Autodesk Inventor part; units mm, degrees
(part 2 of 3)
  spline S257 degree 2 poles (-7.459, 30.0754) (-7.2586, 30.0754) (-7.0197, 30.2886) (-6.9657, 30.489) knots 0 0 0 1 2 2 2
  spline S258 degree 2 poles (-6.9657, 30.489) (-6.9298, 30.6226) (-6.8373, 31.0105) (-6.7988, 31.1389) knots 0 0 0 1 2 2 2
  spline S259 degree 2 poles (-6.7988, 31.1389) (-6.6986, 31.4652) (-6.2953, 31.7683) (-5.9998, 31.7683) knots 0 0 0 1 2 2 2
  spline S260 degree 2 poles (-5.9998, 31.7683) (-5.8123, 31.7683) (-5.4527, 31.6167) (-5.3268, 31.4806) knots 0 0 0 1 2 2 2
  spline S261 degree 2 poles (-5.3268, 31.4806) (-5.1881, 31.329) (-5.0391, 30.9437) (-5.0391, 30.6534) knots 0 0 0 1 2 2 2
  spline S262 degree 2 poles (-6.285, 34.1214) (-5.6839, 34.1214) (-5.0288, 33.5434) (-5.0288, 33.0604) knots 0 0 0 1 2 2 2
  spline S263 degree 2 poles (-5.0288, 33.0604) (-5.0288, 32.5647) (-5.7044, 31.9969) (-6.285, 31.9969) knots 0 0 0 1 2 2 2
  spline S264 degree 2 poles (-6.285, 31.9969) (-6.881, 31.9969) (-7.5412, 32.5826) (-7.5412, 33.0604) knots 0 0 0 1 2 2 2
  spline S265 degree 2 poles (-7.5412, 33.0604) (-7.5412, 33.5434) (-6.8835, 34.1214) (-6.285, 34.1214) knots 0 0 0 1 2 2 2
  spline S266 degree 2 poles (-6.285, 33.7078) (-6.7474, 33.7078) (-7.1969, 33.3713) (-7.1969, 33.0604) knots 0 0 0 1 2 2 2
  spline S267 degree 2 poles (-7.1969, 33.0604) (-7.1969, 32.7496) (-6.7474, 32.4105) (-6.285, 32.4105) knots 0 0 0 1 2 2 2
  spline S268 degree 2 poles (-6.285, 32.4105) (-5.8354, 32.4105) (-5.373, 32.7496) (-5.373, 33.0604) knots 0 0 0 1 2 2 2
  spline S269 degree 2 poles (-5.373, 33.0604) (-5.373, 33.3687) (-5.8277, 33.7078) (-6.285, 33.7078) knots 0 0 0 1 2 2 2
  spline S270 degree 2 poles (-5.0416, 35.4778) (-5.0416, 35.2312) (-5.1932, 34.8227) (-5.3473, 34.6763) knots 0 0 0 1 2 2 2
  spline S271 degree 2 poles (-5.3473, 34.6763) (-5.4989, 34.5298) (-5.9664, 34.368) (-6.2798, 34.368) knots 0 0 0 1 2 2 2
  spline S272 degree 2 poles (-6.2798, 34.368) (-6.5933, 34.368) (-7.0505, 34.535) (-7.2046, 34.6763) knots 0 0 0 1 2 2 2
  spline S273 degree 2 poles (-7.2046, 34.6763) (-7.3613, 34.8176) (-7.5283, 35.2363) (-7.5283, 35.4778) knots 0 0 0 1 2 2 2
  spline S274 degree 2 poles (-7.5283, 35.4778) (-7.5283, 35.673) (-7.4179, 36.0378) (-7.3459, 36.1791) knots 0 0 0 1 2 2 2
  line L206 (-7.3459, 36.1791) -> (-6.8964, 36.1791)
  line L207 (-6.8964, 36.1791) -> (-6.8964, 36.1559)
  spline S275 degree 2 poles (-6.8964, 36.1559) (-6.9323, 36.1123) (-7.0248, 35.9787) (-7.0736, 35.8836) knots 0 0 0 1 2 2 2
  spline S276 degree 2 poles (-7.0736, 35.8836) (-7.1147, 35.7989) (-7.179, 35.5728) (-7.179, 35.4701) knots 0 0 0 1 2 2 2
  spline S277 degree 2 poles (-7.179, 35.4701) (-7.179, 35.1592) (-6.7089, 34.7816) (-6.2798, 34.7816) knots 0 0 0 1 2 2 2
  spline S278 degree 2 poles (-6.2798, 34.7816) (-5.8611, 34.7816) (-5.391, 35.1464) (-5.391, 35.4701) knots 0 0 0 1 2 2 2
  spline S279 degree 2 poles (-5.391, 35.4701) (-5.391, 35.6653) (-5.5529, 36.0198) (-5.6787, 36.1559) knots 0 0 0 1 2 2 2
  line L208 (-5.6787, 36.1559) -> (-5.6787, 36.1791)
  line L209 (-5.6787, 36.1791) -> (-5.2292, 36.1791)
  spline S280 degree 2 poles (-5.2292, 36.1791) (-5.2009, 36.12) (-5.1213, 35.9402) (-5.1033, 35.8682) knots 0 0 0 1 2 2 2
  spline S281 degree 2 poles (-5.1033, 35.8682) (-5.0725, 35.7655) (-5.0416, 35.6036) (-5.0416, 35.4778) knots 0 0 0 1 2 2 2
  line L210 (0.1237, -6.4515) -> (0.1237, -8.4064)
  line L211 (0.1237, -8.4064) -> (-0.3258, -8.4064)
  spline S282 degree 2 poles (-0.3258, -8.4064) (-0.5236, -8.1958) (-0.891, -7.8207) (-1.0888, -7.6409) knots 0 0 0 1 2 2 2
  spline S283 degree 2 poles (-1.0888, -7.6409) (-1.487, -7.2787) (-1.9648, -7.0141) (-2.2191, -7.0141) knots 0 0 0 1 2 2 2
  spline S284 degree 2 poles (-2.2191, -7.0141) (-2.3527, -7.0141) (-2.553, -7.0963) (-2.6173, -7.1708) knots 0 0 0 1 2 2 2
  spline S285 degree 2 poles (-2.6173, -7.1708) (-2.6815, -7.2453) (-2.7457, -7.4405) (-2.7457, -7.5587) knots 0 0 0 1 2 2 2
  spline S286 degree 2 poles (-2.7457, -7.5587) (-2.7457, -7.6717) (-2.6892, -7.9029) (-2.6455, -8.0083) knots 0 0 0 1 2 2 2
  spline S287 degree 2 poles (-2.6455, -8.0083) (-2.6096, -8.0982) (-2.5068, -8.2652) (-2.4708, -8.3165) knots 0 0 0 1 2 2 2
  line L212 (-2.4708, -8.3165) -> (-2.4708, -8.3397)
  line L213 (-2.4708, -8.3397) -> (-2.923, -8.3397)
  spline S288 degree 2 poles (-2.923, -8.3397) (-2.9872, -8.2086) (-3.1131, -7.7385) (-3.1131, -7.5279) knots 0 0 0 1 2 2 2
  spline S289 degree 2 poles (-3.1131, -7.5279) (-3.1131, -7.0835) (-2.643, -6.5825) (-2.2422, -6.5825) knots 0 0 0 1 2 2 2
  spline S290 degree 2 poles (-2.2422, -6.5825) (-2.0547, -6.5825) (-1.7413, -6.6699) (-1.6077, -6.7469) knots 0 0 0 1 2 2 2
  spline S291 degree 2 poles (-1.6077, -6.7469) (-1.469, -6.824) (-1.1967, -7.0475) (-1.0657, -7.1708) knots 0 0 0 1 2 2 2
  spline S292 degree 2 poles (-1.0657, -7.1708) (-0.8473, -7.3712) (-0.3798, -7.8618) (-0.2436, -8.0083) knots 0 0 0 1 2 2 2
  line L214 (-0.2436, -8.0083) -> (-0.2436, -6.4515)
  line L215 (-0.2436, -6.4515) -> (0.1237, -6.4515)
  spline S293 degree 2 poles (-1.4613, -4.0548) (-0.6084, -4.0548) (0.1905, -4.5506) (0.1905, -5.0669) knots 0 0 0 1 2 2 2
  spline S294 degree 2 poles (0.1905, -5.0669) (0.1905, -5.5909) (-0.6238, -6.0816) (-1.4587, -6.0816) knots 0 0 0 1 2 2 2
  spline S295 degree 2 poles (-1.4587, -6.0816) (-2.3167, -6.0816) (-3.1105, -5.5858) (-3.1105, -5.0669) knots 0 0 0 1 2 2 2
  spline S296 degree 2 poles (-3.1105, -5.0669) (-3.1105, -4.5454) (-2.2885, -4.0548) (-1.4613, -4.0548) knots 0 0 0 1 2 2 2
  spline S297 degree 2 poles (-0.4954, -4.5994) (-0.6521, -4.5377) (-1.135, -4.4863) (-1.4613, -4.4863) knots 0 0 0 1 2 2 2
  spline S298 degree 2 poles (-1.4613, -4.4863) (-1.7875, -4.4863) (-2.2679, -4.5377) (-2.4297, -4.6019) knots 0 0 0 1 2 2 2
  spline S299 degree 2 poles (-2.4297, -4.6019) (-2.5916, -4.6662) (-2.7586, -4.8896) (-2.7586, -5.0669) knots 0 0 0 1 2 2 2
  spline S300 degree 2 poles (-2.7586, -5.0669) (-2.7586, -5.2441) (-2.5916, -5.4728) (-2.4246, -5.5396) knots 0 0 0 1 2 2 2
  spline S301 degree 2 poles (-2.4246, -5.5396) (-2.2628, -5.6038) (-1.7695, -5.65) (-1.4587, -5.65) knots 0 0 0 1 2 2 2
  spline S302 degree 2 poles (-1.4587, -5.65) (-1.1247, -5.65) (-0.6778, -5.6089) (-0.5031, -5.5421) knots 0 0 0 1 2 2 2
  spline S303 degree 2 poles (-0.5031, -5.5421) (-0.3387, -5.4805) (-0.1614, -5.2519) (-0.1614, -5.0669) knots 0 0 0 1 2 2 2
  spline S304 degree 2 poles (-0.1614, -5.0669) (-0.1614, -4.8922) (-0.3284, -4.6636) (-0.4954, -4.5994) knots 0 0 0 1 2 2 2
  line L216 (0.1237, -1.694) -> (0.1237, -3.6489)
  line L217 (0.1237, -3.6489) -> (-0.3258, -3.6489)
  spline S305 degree 2 poles (-0.3258, -3.6489) (-0.5236, -3.4382) (-0.891, -3.0632) (-1.0888, -2.8833) knots 0 0 0 1 2 2 2
  spline S306 degree 2 poles (-1.0888, -2.8833) (-1.487, -2.5211) (-1.9648, -2.2565) (-2.2191, -2.2565) knots 0 0 0 1 2 2 2
  spline S307 degree 2 poles (-2.2191, -2.2565) (-2.3527, -2.2565) (-2.553, -2.3387) (-2.6173, -2.4132) knots 0 0 0 1 2 2 2
  spline S308 degree 2 poles (-2.6173, -2.4132) (-2.6815, -2.4877) (-2.7457, -2.683) (-2.7457, -2.8011) knots 0 0 0 1 2 2 2
  spline S309 degree 2 poles (-2.7457, -2.8011) (-2.7457, -2.9142) (-2.6892, -3.1454) (-2.6455, -3.2507) knots 0 0 0 1 2 2 2
  spline S310 degree 2 poles (-2.6455, -3.2507) (-2.6096, -3.3406) (-2.5068, -3.5076) (-2.4708, -3.559) knots 0 0 0 1 2 2 2
  line L218 (-2.4708, -3.559) -> (-2.4708, -3.5821)
  line L219 (-2.4708, -3.5821) -> (-2.923, -3.5821)
  spline S311 degree 2 poles (-2.923, -3.5821) (-2.9872, -3.4511) (-3.1131, -2.981) (-3.1131, -2.7703) knots 0 0 0 1 2 2 2
  spline S312 degree 2 poles (-3.1131, -2.7703) (-3.1131, -2.3259) (-2.643, -1.825) (-2.2422, -1.825) knots 0 0 0 1 2 2 2
  spline S313 degree 2 poles (-2.2422, -1.825) (-2.0547, -1.825) (-1.7413, -1.9123) (-1.6077, -1.9894) knots 0 0 0 1 2 2 2
  spline S314 degree 2 poles (-1.6077, -1.9894) (-1.469, -2.0664) (-1.1967, -2.2899) (-1.0657, -2.4132) knots 0 0 0 1 2 2 2
  spline S315 degree 2 poles (-1.0657, -2.4132) (-0.8473, -2.6136) (-0.3798, -3.1043) (-0.2436, -3.2507) knots 0 0 0 1 2 2 2
  line L220 (-0.2436, -3.2507) -> (-0.2436, -1.694)
  line L221 (-0.2436, -1.694) -> (0.1237, -1.694)
  spline S316 degree 2 poles (-2.7457, -0.4147) (-2.7457, -0.5303) (-2.6892, -0.7589) (-2.6455, -0.8693) knots 0 0 0 1 2 2 2
  spline S317 degree 2 poles (-2.6455, -0.8693) (-2.6019, -0.9721) (-2.5094, -1.1237) (-2.4683, -1.1827) knots 0 0 0 1 2 2 2
  line L222 (-2.4683, -1.1827) -> (-2.4683, -1.2084)
  line L223 (-2.4683, -1.2084) -> (-2.9178, -1.2084)
  spline S318 degree 2 poles (-2.9178, -1.2084) (-2.9923, -1.0697) (-3.1131, -0.5945) (-3.1131, -0.3813) knots 0 0 0 1 2 2 2
  spline S319 degree 2 poles (-3.1131, -0.3813) (-3.1131, -0.1655) (-3.0257, 0.1556) (-2.9332, 0.2867) knots 0 0 0 1 2 2 2
  spline S320 degree 2 poles (-2.9332, 0.2867) (-2.8331, 0.4254) (-2.5428, 0.5692) (-2.3475, 0.5692) knots 0 0 0 1 2 2 2
  spline S321 degree 2 poles (-2.3475, 0.5692) (-2.0855, 0.5692) (-1.6899, 0.225) (-1.6385, -0.0165) knots 0 0 0 1 2 2 2
  line L224 (-1.6385, -0.0165) -> (-1.6077, -0.0165)
  spline S322 degree 2 poles (-1.6077, -0.0165) (-1.5871, 0.0837) (-1.4947, 0.3123) (-1.4022, 0.41) knots 0 0 0 1 2 2 2
  spline S323 degree 2 poles (-1.4022, 0.41) (-1.3123, 0.5076) (-1.0246, 0.6309) (-0.8165, 0.6309) knots 0 0 0 1 2 2 2
  spline S324 degree 2 poles (-0.8165, 0.6309) (-0.6033, 0.6309) (-0.2411, 0.4845) (-0.1023, 0.3509) knots 0 0 0 1 2 2 2
  spline S325 degree 2 poles (-0.1023, 0.3509) (0.0415, 0.2122) (0.1905, -0.1809) (0.1905, -0.4301) knots 0 0 0 1 2 2 2
  spline S326 degree 2 poles (0.1905, -0.4301) (0.1905, -0.669) (0.0749, -1.1365) (-0.0047, -1.2958) knots 0 0 0 1 2 2 2
  line L225 (-0.0047, -1.2958) -> (-0.4543, -1.2958)
  line L226 (-0.4543, -1.2958) -> (-0.4543, -1.265)
  spline S327 degree 2 poles (-0.4543, -1.265) (-0.3567, -1.1314) (-0.1768, -0.6792) (-0.1768, -0.4558) knots 0 0 0 1 2 2 2
  spline S328 degree 2 poles (-0.1768, -0.4558) (-0.1768, -0.3247) (-0.259, -0.0627) (-0.3541, 0.0246) knots 0 0 0 1 2 2 2
  spline S329 degree 2 poles (-0.3541, 0.0246) (-0.4491, 0.1094) (-0.6752, 0.1993) (-0.8473, 0.1993) knots 0 0 0 1 2 2 2
  spline S330 degree 2 poles (-0.8473, 0.1993) (-1.0194, 0.1993) (-1.2429, 0.0991) (-1.3071, 0.0092) knots 0 0 0 1 2 2 2
  spline S331 degree 2 poles (-1.3071, 0.0092) (-1.3714, -0.0807) (-1.4202, -0.3247) (-1.4202, -0.4686) knots 0 0 0 1 2 2 2
  line L227 (-1.4202, -0.4686) -> (-1.4202, -0.6484)
  line L228 (-1.4202, -0.6484) -> (-1.7721, -0.6484)
  line L229 (-1.7721, -0.6484) -> (-1.7721, -0.5071)
  spline S332 degree 2 poles (-1.7721, -0.5071) (-1.7721, -0.222) (-2.0444, 0.1377) (-2.3039, 0.1377) knots 0 0 0 1 2 2 2
  spline S333 degree 2 poles (-2.3039, 0.1377) (-2.4246, 0.1377) (-2.5967, 0.0452) (-2.6481, -0.0293) knots 0 0 0 1 2 2 2
  spline S334 degree 2 poles (-2.6481, -0.0293) (-2.702, -0.109) (-2.7457, -0.3042) (-2.7457, -0.4147) knots 0 0 0 1 2 2 2
  spline S335 degree 2 poles (-2.7457, 1.9641) (-2.7457, 1.8485) (-2.6892, 1.6199) (-2.6455, 1.5094) knots 0 0 0 1 2 2 2
  spline S336 degree 2 poles (-2.6455, 1.5094) (-2.6019, 1.4067) (-2.5094, 1.2551) (-2.4683, 1.196) knots 0 0 0 1 2 2 2
  line L230 (-2.4683, 1.196) -> (-2.4683, 1.1703)
  line L231 (-2.4683, 1.1703) -> (-2.9178, 1.1703)
  spline S337 degree 2 poles (-2.9178, 1.1703) (-2.9923, 1.3091) (-3.1131, 1.7843) (-3.1131, 1.9975) knots 0 0 0 1 2 2 2
  spline S338 degree 2 poles (-3.1131, 1.9975) (-3.1131, 2.2133) (-3.0257, 2.5344) (-2.9332, 2.6654) knots 0 0 0 1 2 2 2
  spline S339 degree 2 poles (-2.9332, 2.6654) (-2.8331, 2.8042) (-2.5428, 2.948) (-2.3475, 2.948) knots 0 0 0 1 2 2 2
  spline S340 degree 2 poles (-2.3475, 2.948) (-2.0855, 2.948) (-1.6899, 2.6038) (-1.6385, 2.3623) knots 0 0 0 1 2 2 2
  line L232 (-1.6385, 2.3623) -> (-1.6077, 2.3623)
  spline S341 degree 2 poles (-1.6077, 2.3623) (-1.5871, 2.4625) (-1.4947, 2.6911) (-1.4022, 2.7887) knots 0 0 0 1 2 2 2
  spline S342 degree 2 poles (-1.4022, 2.7887) (-1.3123, 2.8864) (-1.0246, 3.0097) (-0.8165, 3.0097) knots 0 0 0 1 2 2 2
  spline S343 degree 2 poles (-0.8165, 3.0097) (-0.6033, 3.0097) (-0.2411, 2.8632) (-0.1023, 2.7297) knots 0 0 0 1 2 2 2
  spline S344 degree 2 poles (-0.1023, 2.7297) (0.0415, 2.5909) (0.1905, 2.1979) (0.1905, 1.9487) knots 0 0 0 1 2 2 2
  spline S345 degree 2 poles (0.1905, 1.9487) (0.1905, 1.7098) (0.0749, 1.2423) (-0.0047, 1.083) knots 0 0 0 1 2 2 2
  line L233 (-0.0047, 1.083) -> (-0.4543, 1.083)
  line L234 (-0.4543, 1.083) -> (-0.4543, 1.1138)
  spline S346 degree 2 poles (-0.4543, 1.1138) (-0.3567, 1.2474) (-0.1768, 1.6995) (-0.1768, 1.923) knots 0 0 0 1 2 2 2
  spline S347 degree 2 poles (-0.1768, 1.923) (-0.1768, 2.054) (-0.259, 2.3161) (-0.3541, 2.4034) knots 0 0 0 1 2 2 2
  spline S348 degree 2 poles (-0.3541, 2.4034) (-0.4491, 2.4882) (-0.6752, 2.5781) (-0.8473, 2.5781) knots 0 0 0 1 2 2 2
  spline S349 degree 2 poles (-0.8473, 2.5781) (-1.0194, 2.5781) (-1.2429, 2.4779) (-1.3071, 2.388) knots 0 0 0 1 2 2 2
  spline S350 degree 2 poles (-1.3071, 2.388) (-1.3714, 2.2981) (-1.4202, 2.054) (-1.4202, 1.9102) knots 0 0 0 1 2 2 2
  line L235 (-1.4202, 1.9102) -> (-1.4202, 1.7304)
  line L236 (-1.4202, 1.7304) -> (-1.7721, 1.7304)
  line L237 (-1.7721, 1.7304) -> (-1.7721, 1.8717)
  spline S351 degree 2 poles (-1.7721, 1.8717) (-1.7721, 2.1568) (-2.0444, 2.5164) (-2.3039, 2.5164) knots 0 0 0 1 2 2 2
  spline S352 degree 2 poles (-2.3039, 2.5164) (-2.4246, 2.5164) (-2.5967, 2.424) (-2.6481, 2.3495) knots 0 0 0 1 2 2 2
  spline S353 degree 2 poles (-2.6481, 2.3495) (-2.702, 2.2698) (-2.7457, 2.0746) (-2.7457, 1.9641) knots 0 0 0 1 2 2 2
  spline S354 degree 2 poles (-1.4613, 5.4604) (-0.6084, 5.4604) (0.1905, 4.9646) (0.1905, 4.4482) knots 0 0 0 1 2 2 2
  spline S355 degree 2 poles (0.1905, 4.4482) (0.1905, 3.9242) (-0.6238, 3.4335) (-1.4587, 3.4335) knots 0 0 0 1 2 2 2
  spline S356 degree 2 poles (-1.4587, 3.4335) (-2.3167, 3.4335) (-3.1105, 3.9293) (-3.1105, 4.4482) knots 0 0 0 1 2 2 2
  spline S357 degree 2 poles (-3.1105, 4.4482) (-3.1105, 4.9697) (-2.2885, 5.4604) (-1.4613, 5.4604) knots 0 0 0 1 2 2 2
  spline S358 degree 2 poles (-0.4954, 4.9158) (-0.6521, 4.9774) (-1.135, 5.0288) (-1.4613, 5.0288) knots 0 0 0 1 2 2 2
  spline S359 degree 2 poles (-1.4613, 5.0288) (-1.7875, 5.0288) (-2.2679, 4.9774) (-2.4297, 4.9132) knots 0 0 0 1 2 2 2
  spline S360 degree 2 poles (-2.4297, 4.9132) (-2.5916, 4.849) (-2.7586, 4.6255) (-2.7586, 4.4482) knots 0 0 0 1 2 2 2
  spline S361 degree 2 poles (-2.7586, 4.4482) (-2.7586, 4.271) (-2.5916, 4.0424) (-2.4246, 3.9756) knots 0 0 0 1 2 2 2
  spline S362 degree 2 poles (-2.4246, 3.9756) (-2.2628, 3.9113) (-1.7695, 3.8651) (-1.4587, 3.8651) knots 0 0 0 1 2 2 2
  spline S363 degree 2 poles (-1.4587, 3.8651) (-1.1247, 3.8651) (-0.6778, 3.9062) (-0.5031, 3.973) knots 0 0 0 1 2 2 2
  spline S364 degree 2 poles (-0.5031, 3.973) (-0.3387, 4.0347) (-0.1614, 4.2633) (-0.1614, 4.4482) knots 0 0 0 1 2 2 2
  spline S365 degree 2 poles (-0.1614, 4.4482) (-0.1614, 4.6229) (-0.3284, 4.8516) (-0.4954, 4.9158) knots 0 0 0 1 2 2 2
  spline S366 degree 2 poles (-2.7457, 6.7217) (-2.7457, 6.6061) (-2.6892, 6.3775) (-2.6455, 6.267) knots 0 0 0 1 2 2 2
  spline S367 degree 2 poles (-2.6455, 6.267) (-2.6019, 6.1643) (-2.5094, 6.0127) (-2.4683, 5.9536) knots 0 0 0 1 2 2 2
  line L238 (-2.4683, 5.9536) -> (-2.4683, 5.9279)
  line L239 (-2.4683, 5.9279) -> (-2.9178, 5.9279)
  spline S368 degree 2 poles (-2.9178, 5.9279) (-2.9923, 6.0666) (-3.1131, 6.5419) (-3.1131, 6.7551) knots 0 0 0 1 2 2 2
  spline S369 degree 2 poles (-3.1131, 6.7551) (-3.1131, 6.9709) (-3.0257, 7.292) (-2.9332, 7.423) knots 0 0 0 1 2 2 2
  spline S370 degree 2 poles (-2.9332, 7.423) (-2.8331, 7.5617) (-2.5428, 7.7056) (-2.3475, 7.7056) knots 0 0 0 1 2 2 2
  spline S371 degree 2 poles (-2.3475, 7.7056) (-2.0855, 7.7056) (-1.6899, 7.3614) (-1.6385, 7.1199) knots 0 0 0 1 2 2 2
  line L240 (-1.6385, 7.1199) -> (-1.6077, 7.1199)
  spline S372 degree 2 poles (-1.6077, 7.1199) (-1.5871, 7.2201) (-1.4947, 7.4487) (-1.4022, 7.5463) knots 0 0 0 1 2 2 2
  spline S373 degree 2 poles (-1.4022, 7.5463) (-1.3123, 7.6439) (-1.0246, 7.7672) (-0.8165, 7.7672) knots 0 0 0 1 2 2 2
  spline S374 degree 2 poles (-0.8165, 7.7672) (-0.6033, 7.7672) (-0.2411, 7.6208) (-0.1023, 7.4872) knots 0 0 0 1 2 2 2
  spline S375 degree 2 poles (-0.1023, 7.4872) (0.0415, 7.3485) (0.1905, 6.9555) (0.1905, 6.7063) knots 0 0 0 1 2 2 2
  spline S376 degree 2 poles (0.1905, 6.7063) (0.1905, 6.4674) (0.0749, 5.9998) (-0.0047, 5.8406) knots 0 0 0 1 2 2 2
  line L241 (-0.0047, 5.8406) -> (-0.4543, 5.8406)
  line L242 (-0.4543, 5.8406) -> (-0.4543, 5.8714)
  spline S377 degree 2 poles (-0.4543, 5.8714) (-0.3567, 6.005) (-0.1768, 6.4571) (-0.1768, 6.6806) knots 0 0 0 1 2 2 2
  spline S378 degree 2 poles (-0.1768, 6.6806) (-0.1768, 6.8116) (-0.259, 7.0736) (-0.3541, 7.161) knots 0 0 0 1 2 2 2
  spline S379 degree 2 poles (-0.3541, 7.161) (-0.4491, 7.2458) (-0.6752, 7.3357) (-0.8473, 7.3357) knots 0 0 0 1 2 2 2
  spline S380 degree 2 poles (-0.8473, 7.3357) (-1.0194, 7.3357) (-1.2429, 7.2355) (-1.3071, 7.1456) knots 0 0 0 1 2 2 2
  spline S381 degree 2 poles (-1.3071, 7.1456) (-1.3714, 7.0557) (-1.4202, 6.8116) (-1.4202, 6.6678) knots 0 0 0 1 2 2 2
  line L243 (-1.4202, 6.6678) -> (-1.4202, 6.4879)
  line L244 (-1.4202, 6.4879) -> (-1.7721, 6.4879)
  line L245 (-1.7721, 6.4879) -> (-1.7721, 6.6292)
  spline S382 degree 2 poles (-1.7721, 6.6292) (-1.7721, 6.9144) (-2.0444, 7.274) (-2.3039, 7.274) knots 0 0 0 1 2 2 2
  spline S383 degree 2 poles (-2.3039, 7.274) (-2.4246, 7.274) (-2.5967, 7.1815) (-2.6481, 7.107) knots 0 0 0 1 2 2 2
  spline S384 degree 2 poles (-2.6481, 7.107) (-2.702, 7.0274) (-2.7457, 6.8322) (-2.7457, 6.7217) knots 0 0 0 1 2 2 2
  spline S385 degree 2 poles (0.1957, 9.2032) (0.1957, 8.9669) (0.0544, 8.579) (-0.0766, 8.4429) knots 0 0 0 1 2 2 2
  spline S386 degree 2 poles (-0.0766, 8.4429) (-0.2051, 8.3093) (-0.5545, 8.1706) (-0.7523, 8.1706) knots 0 0 0 1 2 2 2
  spline S387 degree 2 poles (-0.7523, 8.1706) (-1.0091, 8.1706) (-1.4407, 8.4454) (-1.5692, 8.7074) knots 0 0 0 1 2 2 2
  line L246 (-1.5692, 8.7074) -> (-1.582, 8.7074)
  spline S388 degree 2 poles (-1.582, 8.7074) (-1.7182, 8.4737) (-2.0418, 8.2476) (-2.2833, 8.2476) knots 0 0 0 1 2 2 2
  spline S389 degree 2 poles (-2.2833, 8.2476) (-2.6404, 8.2476) (-3.1182, 8.7871) (-3.1182, 9.2032) knots 0 0 0 1 2 2 2
  spline S390 degree 2 poles (-3.1182, 9.2032) (-3.1182, 9.6348) (-2.6661, 10.1563) (-2.3116, 10.1563) knots 0 0 0 1 2 2 2
  spline S391 degree 2 poles (-2.3116, 10.1563) (-2.0984, 10.1563) (-1.6822, 9.9071) (-1.564, 9.6733) knots 0 0 0 1 2 2 2
  line L247 (-1.564, 9.6733) -> (-1.5512, 9.6733)
  spline S392 degree 2 poles (-1.5512, 9.6733) (-1.4227, 9.9508) (-1.0528, 10.2359) (-0.76, 10.2359) knots 0 0 0 1 2 2 2
  spline S393 degree 2 poles (-0.76, 10.2359) (-0.3541, 10.2359) (0.1957, 9.6451) (0.1957, 9.2032) knots 0 0 0 1 2 2 2
  spline S394 degree 2 poles (-0.7189, 9.7992) (-0.9141, 9.7992) (-1.1453, 9.6451) (-1.2635, 9.4267) knots 0 0 0 1 2 2 2
  spline S395 degree 2 poles (-1.2635, 9.4267) (-1.3046, 9.3548) (-1.3996, 9.1133) (-1.4613, 8.9618) knots 0 0 0 1 2 2 2
  spline S396 degree 2 poles (-1.4613, 8.9618) (-1.3457, 8.7871) (-1.0014, 8.5996) (-0.7831, 8.5996) knots 0 0 0 1 2 2 2
  spline S397 degree 2 poles (-0.7831, 8.5996) (-0.4954, 8.5996) (-0.1203, 8.9464) (-0.1203, 9.2084) knots 0 0 0 1 2 2 2
  spline S398 degree 2 poles (-0.1203, 9.2084) (-0.1203, 9.4755) (-0.4414, 9.7992) (-0.7189, 9.7992) knots 0 0 0 1 2 2 2
  spline S399 degree 2 poles (-2.3064, 9.7401) (-2.5197, 9.7401) (-2.8048, 9.455) (-2.8048, 9.2007) knots 0 0 0 1 2 2 2
  spline S400 degree 2 poles (-2.8048, 9.2007) (-2.8048, 8.9695) (-2.5505, 8.6741) (-2.3321, 8.6741) knots 0 0 0 1 2 2 2
  spline S401 degree 2 poles (-2.3321, 8.6741) (-2.1754, 8.6741) (-1.9571, 8.8256) (-1.8697, 8.9772) knots 0 0 0 1 2 2 2
  spline S402 degree 2 poles (-1.8697, 8.9772) (-1.8338, 9.0414) (-1.7079, 9.3137) (-1.6719, 9.4242) knots 0 0 0 1 2 2 2
  spline S403 degree 2 poles (-1.6719, 9.4242) (-1.8132, 9.6091) (-2.1138, 9.7401) (-2.3064, 9.7401) knots 0 0 0 1 2 2 2
  spline S404 degree 2 poles (-2.0162, 10.5365) (-2.2602, 10.5365) (-2.6661, 10.6958) (-2.8125, 10.8345) knots 0 0 0 1 2 2 2
  spline S405 degree 2 poles (-2.8125, 10.8345) (-2.9538, 10.9655) (-3.1105, 11.3483) (-3.1105, 11.5435) knots 0 0 0 1 2 2 2
  spline S406 degree 2 poles (-3.1105, 11.5435) (-3.1105, 11.7618) (-2.9641, 12.1164) (-2.8253, 12.2474) knots 0 0 0 1 2 2 2
  spline S407 degree 2 poles (-2.8253, 12.2474) (-2.6507, 12.4118) (-2.0855, 12.5916) (-1.6514, 12.5916) knots 0 0 0 1 2 2 2
  spline S408 degree 2 poles (-1.6514, 12.5916) (-1.2583, 12.5916) (-0.5545, 12.4143) (-0.3207, 12.2422) knots 0 0 0 1 2 2 2
  spline S409 degree 2 poles (-0.3207, 12.2422) (-0.0741, 12.0598) (0.1854, 11.5461) (0.1854, 11.171) knots 0 0 0 1 2 2 2
  spline S410 degree 2 poles (0.1854, 11.171) (0.1854, 11.0862) (0.1674, 10.8936) (0.1417, 10.8114) knots 0 0 0 1 2 2 2
  line L248 (0.1417, 10.8114) -> (-0.2667, 10.8114)
  line L249 (-0.2667, 10.8114) -> (-0.2667, 10.8319)
  spline S411 degree 2 poles (-0.2667, 10.8319) (-0.2359, 10.8859) (-0.182, 11.1119) (-0.182, 11.2275) knots 0 0 0 1 2 2 2
  spline S412 degree 2 poles (-0.182, 11.2275) (-0.182, 11.6437) (-0.7317, 12.1189) (-1.2403, 12.1523) knots 0 0 0 1 2 2 2
  spline S413 degree 2 poles (-1.2403, 12.1523) (-1.1247, 11.9828) (-1.0194, 11.6745) (-1.0194, 11.4921) knots 0 0 0 1 2 2 2
  spline S414 degree 2 poles (-1.0194, 11.4921) (-1.0194, 11.3174) (-1.0965, 11.0271) (-1.207, 10.8807) knots 0 0 0 1 2 2 2
  spline S415 degree 2 poles (-1.207, 10.8807) (-1.338, 10.7112) (-1.7361, 10.5365) (-2.0162, 10.5365) knots 0 0 0 1 2 2 2
  spline S416 degree 2 poles (-1.7464, 12.1626) (-2.0675, 12.1626) (-2.4734, 12.0444) (-2.5839, 11.9391) knots 0 0 0 1 2 2 2
  spline S417 degree 2 poles (-2.5839, 11.9391) (-2.6866, 11.8466) (-2.7637, 11.654) (-2.7637, 11.5409) knots 0 0 0 1 2 2 2
  spline S418 degree 2 poles (-2.7637, 11.5409) (-2.7637, 11.2789) (-2.3886, 10.9681) (-2.0341, 10.9681) knots 0 0 0 1 2 2 2
  spline S419 degree 2 poles (-2.0341, 10.9681) (-1.8338, 10.9681) (-1.5743, 11.0708) (-1.4818, 11.1838) knots 0 0 0 1 2 2 2
  spline S420 degree 2 poles (-1.4818, 11.1838) (-1.415, 11.2661) (-1.3714, 11.469) (-1.3714, 11.5872) knots 0 0 0 1 2 2 2
  spline S421 degree 2 poles (-1.3714, 11.5872) (-1.3714, 11.7233) (-1.4664, 12.0367) (-1.546, 12.1549) knots 0 0 0 1 2 2 2
  spline S422 degree 2 poles (-1.546, 12.1549) (-1.5769, 12.1575) (-1.6822, 12.1626) (-1.7464, 12.1626) knots 0 0 0 1 2 2 2
  line L250 (10.312, -23.8361) -> (10.312, -24.3622)
  line L251 (10.312, -24.3622) -> (8.8942, -25.4762)
  line L252 (8.8942, -25.4762) -> (9.0943, -25.6541)
  line L253 (9.0943, -25.6541) -> (10.312, -25.6541)
  line L254 (10.312, -25.6541) -> (10.312, -26.0591)
  line L255 (10.312, -26.0591) -> (7.264, -26.0591)
  line L256 (7.264, -26.0591) -> (7.264, -25.6541)
  line L257 (7.264, -25.6541) -> (8.6645, -25.6541)
  line L258 (8.6645, -25.6541) -> (7.264, -24.4042)
  line L259 (7.264, -24.4042) -> (7.264, -23.9102)
  line L260 (7.264, -23.9102) -> (8.625, -25.1724)
  line L261 (8.625, -25.1724) -> (10.312, -23.8361)
  spline S423 degree 2 poles (10.3639, -22.6308) (10.3639, -23.1791) (9.7488, -23.7818) (9.1807, -23.7818) knots 0 0 0 1 2 2 2
  spline S424 degree 2 poles (9.1807, -23.7818) (8.6225, -23.7818) (7.9606, -23.1964) (7.9606, -22.7246) knots 0 0 0 1 2 2 2
  spline S425 degree 2 poles (7.9606, -22.7246) (7.9606, -22.5122) (8.0841, -22.1837) (8.215, -22.0627) knots 0 0 0 1 2 2 2
  spline S426 degree 2 poles (8.215, -22.0627) (8.3459, -21.9392) (8.7238, -21.8082) (8.998, -21.8082) knots 0 0 0 1 2 2 2
  line L262 (8.998, -21.8082) -> (9.2079, -21.8082)
  line L263 (9.2079, -21.8082) -> (9.2079, -23.3915)
  spline S427 degree 2 poles (9.2079, -23.3915) (9.6056, -23.3915) (10.028, -22.9914) (10.028, -22.6357) knots 0 0 0 1 2 2 2
  spline S428 degree 2 poles (10.028, -22.6357) (10.028, -22.5097) (9.9712, -22.2652) (9.9267, -22.1664) knots 0 0 0 1 2 2 2
  spline S429 degree 2 poles (9.9267, -22.1664) (9.8773, -22.0627) (9.7908, -21.9194) (9.7513, -21.8725) knots 0 0 0 1 2 2 2
  line L264 (9.7513, -21.8725) -> (9.7513, -21.8502)
  line L265 (9.7513, -21.8502) -> (10.1712, -21.8502)
  spline S430 degree 2 poles (10.1712, -21.8502) (10.1984, -21.9169) (10.2774, -22.1195) (10.2997, -22.1985) knots 0 0 0 1 2 2 2
  spline S431 degree 2 poles (10.2997, -22.1985) (10.3318, -22.3097) (10.3639, -22.4924) (10.3639, -22.6308) knots 0 0 0 1 2 2 2
  spline S432 degree 2 poles (8.914, -22.1837) (8.7584, -22.1886) (8.5311, -22.2528) (8.4546, -22.3146) knots 0 0 0 1 2 2 2
  spline S433 degree 2 poles (8.4546, -22.3146) (8.3681, -22.3813) (8.2767, -22.5912) (8.2767, -22.7469) knots 0 0 0 1 2 2 2
  spline S434 degree 2 poles (8.2767, -22.7469) (8.2767, -22.9) (8.3681, -23.1149) (8.457, -23.2038) knots 0 0 0 1 2 2 2
  spline S435 degree 2 poles (8.457, -23.2038) (8.5484, -23.2903) (8.7683, -23.3792) (8.914, -23.3915) knots 0 0 0 1 2 2 2
  line L266 (8.914, -23.3915) -> (8.914, -22.1837)
  line L267 (10.312, -19.6223) -> (10.312, -20.0076)
  line L268 (10.312, -20.0076) -> (9.0078, -20.0076)
  spline S436 degree 2 poles (9.0078, -20.0076) (8.8498, -20.0076) (8.5781, -20.0372) (8.4966, -20.0817) knots 0 0 0 1 2 2 2
  spline S437 degree 2 poles (8.4966, -20.0817) (8.4101, -20.1286) (8.3261, -20.2966) (8.3261, -20.4399) knots 0 0 0 1 2 2 2
  spline S438 degree 2 poles (8.3261, -20.4399) (8.3261, -20.5831) (8.4793, -20.8869) (8.6028, -21.0327) knots 0 0 0 1 2 2 2
  line L269 (8.6028, -21.0327) -> (10.312, -21.0327)
  line L270 (10.312, -21.0327) -> (10.312, -21.418)
  line L271 (10.312, -21.418) -> (8.0248, -21.418)
  line L272 (8.0248, -21.418) -> (8.0248, -21.0327)
  line L273 (8.0248, -21.0327) -> (8.2792, -21.0327)
  spline S439 degree 2 poles (8.2792, -21.0327) (8.1236, -20.8598) (7.9606, -20.5263) (7.9606, -20.3386) knots 0 0 0 1 2 2 2
  spline S440 degree 2 poles (7.9606, -20.3386) (7.9606, -20.0027) (8.4052, -19.6223) (8.8275, -19.6223) knots 0 0 0 1 2 2 2
  line L274 (8.8275, -19.6223) -> (10.312, -19.6223)
  line L275 (10.312, -17.2856) -> (10.312, -17.671)
  line L276 (10.312, -17.671) -> (9.0078, -17.671)
  spline S441 degree 2 poles (9.0078, -17.671) (8.8498, -17.671) (8.5781, -17.7006) (8.4966, -17.7451) knots 0 0 0 1 2 2 2
  spline S442 degree 2 poles (8.4966, -17.7451) (8.4101, -17.792) (8.3261, -17.96) (8.3261, -18.1032) knots 0 0 0 1 2 2 2
  spline S443 degree 2 poles (8.3261, -18.1032) (8.3261, -18.2465) (8.4793, -18.5503) (8.6028, -18.696) knots 0 0 0 1 2 2 2
  line L277 (8.6028, -18.696) -> (10.312, -18.696)
  line L278 (10.312, -18.696) -> (10.312, -19.0813)
  line L279 (10.312, -19.0813) -> (8.0248, -19.0813)
  line L280 (8.0248, -19.0813) -> (8.0248, -18.696)
  line L281 (8.0248, -18.696) -> (8.2792, -18.696)
  spline S444 degree 2 poles (8.2792, -18.696) (8.1236, -18.5231) (7.9606, -18.1897) (7.9606, -18.002) knots 0 0 0 1 2 2 2
  spline S445 degree 2 poles (7.9606, -18.002) (7.9606, -17.666) (8.4052, -17.2856) (8.8275, -17.2856) knots 0 0 0 1 2 2 2
  line L282 (8.8275, -17.2856) -> (10.312, -17.2856)
  line L283 (8.0248, -14.949) -> (11.1543, -16.1791)
  line L284 (11.1543, -16.1791) -> (11.1543, -16.5916)
  line L285 (11.1543, -16.5916) -> (10.2009, -16.1815)
  line L286 (10.2009, -16.1815) -> (8.0248, -17.0115)
  line L287 (8.0248, -17.0115) -> (8.0248, -16.5965)
  line L288 (8.0248, -16.5965) -> (9.7192, -15.9716)
  line L289 (9.7192, -15.9716) -> (8.0248, -15.3492)
  line L290 (8.0248, -15.3492) -> (8.0248, -14.949)
  line L291 (10.312, -13.6473) -> (7.264, -12.6198)
  line L292 (7.264, -12.6198) -> (7.264, -12.1208)
  line L293 (7.264, -12.1208) -> (10.312, -11.0933)
  line L294 (10.312, -11.0933) -> (10.312, -11.5206)
  line L295 (10.312, -11.5206) -> (9.4599, -11.7973)
  line L296 (9.4599, -11.7973) -> (9.4599, -12.9606)
  line L297 (9.4599, -12.9606) -> (10.312, -13.2373)
  line L298 (10.312, -13.2373) -> (10.312, -13.6473)
  line L299 (9.1141, -11.9084) -> (7.679, -12.3802)
  line L300 (7.679, -12.3802) -> (9.1141, -12.8495)
  line L301 (9.1141, -12.8495) -> (9.1141, -11.9084)
  line L302 (10.312, -10.4412) -> (10.312, -10.8266)
  line L303 (10.312, -10.8266) -> (7.1282, -10.8266)
  line L304 (7.1282, -10.8266) -> (7.1282, -10.4412)
  line L305 (7.1282, -10.4412) -> (10.312, -10.4412)
  spline S446 degree 2 poles (10.3639, -8.8827) (10.3639, -9.431) (9.7488, -10.0337) (9.1807, -10.0337) knots 0 0 0 1 2 2 2
  spline S447 degree 2 poles (9.1807, -10.0337) (8.6225, -10.0337) (7.9606, -9.4483) (7.9606, -8.9765) knots 0 0 0 1 2 2 2
  spline S448 degree 2 poles (7.9606, -8.9765) (7.9606, -8.7641) (8.0841, -8.4356) (8.215, -8.3145) knots 0 0 0 1 2 2 2
  spline S449 degree 2 poles (8.215, -8.3145) (8.3459, -8.191) (8.7238, -8.0601) (8.998, -8.0601) knots 0 0 0 1 2 2 2
  line L306 (8.998, -8.0601) -> (9.2079, -8.0601)
  line L307 (9.2079, -8.0601) -> (9.2079, -9.6434)
  spline S450 degree 2 poles (9.2079, -9.6434) (9.6056, -9.6434) (10.028, -9.2433) (10.028, -8.8876) knots 0 0 0 1 2 2 2
  spline S451 degree 2 poles (10.028, -8.8876) (10.028, -8.7616) (9.9712, -8.5171) (9.9267, -8.4183) knots 0 0 0 1 2 2 2
  spline S452 degree 2 poles (9.9267, -8.4183) (9.8773, -8.3145) (9.7908, -8.1713) (9.7513, -8.1244) knots 0 0 0 1 2 2 2
  line L308 (9.7513, -8.1244) -> (9.7513, -8.1021)
  line L309 (9.7513, -8.1021) -> (10.1712, -8.1021)
  spline S453 degree 2 poles (10.1712, -8.1021) (10.1984, -8.1688) (10.2774, -8.3714) (10.2997, -8.4504) knots 0 0 0 1 2 2 2
  spline S454 degree 2 poles (10.2997, -8.4504) (10.3318, -8.5615) (10.3639, -8.7443) (10.3639, -8.8827) knots 0 0 0 1 2 2 2
  spline S455 degree 2 poles (8.914, -8.4356) (8.7584, -8.4405) (8.5311, -8.5047) (8.4546, -8.5665) knots 0 0 0 1 2 2 2
  spline S456 degree 2 poles (8.4546, -8.5665) (8.3681, -8.6332) (8.2767, -8.8431) (8.2767, -8.9987) knots 0 0 0 1 2 2 2
  spline S457 degree 2 poles (8.2767, -8.9987) (8.2767, -9.1519) (8.3681, -9.3668) (8.457, -9.4557) knots 0 0 0 1 2 2 2
  spline S458 degree 2 poles (8.457, -9.4557) (8.5484, -9.5421) (8.7683, -9.6311) (8.914, -9.6434) knots 0 0 0 1 2 2 2
  line L310 (8.914, -9.6434) -> (8.914, -8.4356)
  line L311 (10.312, -5.8939) -> (10.312, -6.3657)
  line L312 (10.312, -6.3657) -> (9.4524, -6.9215)
  line L313 (9.4524, -6.9215) -> (10.312, -7.492)
  line L314 (10.312, -7.492) -> (10.312, -7.9292)
  line L315 (10.312, -7.9292) -> (9.1783, -7.1363)
  line L316 (9.1783, -7.1363) -> (8.0248, -7.9218)
  line L317 (8.0248, -7.9218) -> (8.0248, -7.45)
  line L318 (8.0248, -7.45) -> (8.8769, -6.8968)
  line L319 (8.8769, -6.8968) -> (8.0248, -6.3311)
  line L320 (8.0248, -6.3311) -> (8.0248, -5.8939)
  line L321 (8.0248, -5.8939) -> (9.1536, -6.6819)
  line L322 (9.1536, -6.6819) -> (10.312, -5.8939)
  spline S459 degree 2 poles (10.07, -4.3205) (10.1045, -4.3675) (10.228, -4.5255) (10.2651, -4.5996) knots 0 0 0 1 2 2 2
  spline S460 degree 2 poles (10.2651, -4.5996) (10.3194, -4.7009) (10.3762, -4.8911) (10.3762, -5.064) knots 0 0 0 1 2 2 2
  spline S461 degree 2 poles (10.3762, -5.064) (10.3762, -5.2048) (10.27, -5.4592) (10.1737, -5.5555) knots 0 0 0 1 2 2 2
  spline S462 degree 2 poles (10.1737, -5.5555) (10.0798, -5.6469) (9.8032, -5.7581) (9.65, -5.7581) knots 0 0 0 1 2 2 2
  spline S463 degree 2 poles (9.65, -5.7581) (9.4129, -5.7581) (9.077, -5.558) (8.9807, -5.3406) knots 0 0 0 1 2 2 2
  spline S464 degree 2 poles (8.9807, -5.3406) (8.8918, -5.148) (8.8251, -4.6243) (8.8078, -4.3205) knots 0 0 0 1 2 2 2
  line L323 (8.8078, -4.3205) -> (8.7337, -4.3205)
  spline S465 degree 2 poles (8.7337, -4.3205) (8.6003, -4.3205) (8.4348, -4.402) (8.3879, -4.4761) knots 0 0 0 1 2 2 2
  spline S466 degree 2 poles (8.3879, -4.4761) (8.3409, -4.5502) (8.3113, -4.7627) (8.3113, -4.8763) knots 0 0 0 1 2 2 2
  spline S467 degree 2 poles (8.3113, -4.8763) (8.3113, -5.0097) (8.3903, -5.3703) (8.4669, -5.5506) knots 0 0 0 1 2 2 2
  line L324 (8.4669, -5.5506) -> (8.4669, -5.5728)
  line L325 (8.4669, -5.5728) -> (8.0742, -5.5728)
  spline S468 degree 2 poles (8.0742, -5.5728) (8.0445, -5.4666) (7.9704, -5.0689) (7.9704, -4.8738) knots 0 0 0 1 2 2 2
  spline S469 degree 2 poles (7.9704, -4.8738) (7.9704, -4.6367) (8.0445, -4.3131) (8.1409, -4.1847) knots 0 0 0 1 2 2 2
  spline S470 degree 2 poles (8.1409, -4.1847) (8.2347, -4.0587) (8.5336, -3.9352) (8.7485, -3.9352) knots 0 0 0 1 2 2 2
  line L326 (8.7485, -3.9352) -> (10.312, -3.9352)
  line L327 (10.312, -3.9352) -> (10.312, -4.3205)
  line L328 (10.312, -4.3205) -> (10.07, -4.3205)
  line L329 (9.7488, -4.3205) -> (9.1141, -4.3205)
  spline S471 degree 2 poles (9.1141, -4.3205) (9.1264, -4.4589) (9.1684, -4.8763) (9.2079, -5.0072) knots 0 0 0 1 2 2 2
  spline S472 degree 2 poles (9.2079, -5.0072) (9.2548, -5.1603) (9.45, -5.3604) (9.6229, -5.3604) knots 0 0 0 1 2 2 2
  spline S473 degree 2 poles (9.6229, -5.3604) (9.8205, -5.3604) (10.0206, -5.1381) (10.0206, -4.9257) knots 0 0 0 1 2 2 2
  spline S474 degree 2 poles (10.0206, -4.9257) (10.0206, -4.7454) (9.8649, -4.449) (9.7488, -4.3205) knots 0 0 0 1 2 2 2
  line L330 (10.312, -1.5986) -> (10.312, -1.9839)
  line L331 (10.312, -1.9839) -> (9.0078, -1.9839)
  spline S475 degree 2 poles (9.0078, -1.9839) (8.8498, -1.9839) (8.5781, -2.0135) (8.4966, -2.058) knots 0 0 0 1 2 2 2
  spline S476 degree 2 poles (8.4966, -2.058) (8.4101, -2.1049) (8.3261, -2.2729) (8.3261, -2.4161) knots 0 0 0 1 2 2 2
  spline S477 degree 2 poles (8.3261, -2.4161) (8.3261, -2.5594) (8.4793, -2.8632) (8.6028, -3.009) knots 0 0 0 1 2 2 2
  line L332 (8.6028, -3.009) -> (10.312, -3.009)
  line L333 (10.312, -3.009) -> (10.312, -3.3943)
  line L334 (10.312, -3.3943) -> (8.0248, -3.3943)
  line L335 (8.0248, -3.3943) -> (8.0248, -3.009)
  line L336 (8.0248, -3.009) -> (8.2792, -3.009)
  spline S478 degree 2 poles (8.2792, -3.009) (8.1236, -2.8361) (7.9606, -2.5026) (7.9606, -2.3149) knots 0 0 0 1 2 2 2
  spline S479 degree 2 poles (7.9606, -2.3149) (7.9606, -1.979) (8.4052, -1.5986) (8.8275, -1.5986) knots 0 0 0 1 2 2 2
  line L337 (8.8275, -1.5986) -> (10.312, -1.5986)
  line L338 (10.312, 0.701) -> (10.312, 0.3157)
  line L339 (10.312, 0.3157) -> (10.0798, 0.3157)
  spline S480 degree 2 poles (10.0798, 0.3157) (10.1539, 0.2268) (10.2527, 0.0959) (10.2947, 0.0069) knots 0 0 0 1 2 2 2
  spline S481 degree 2 poles (10.2947, 0.0069) (10.3342, -0.0746) (10.3762, -0.2499) (10.3762, -0.366) knots 0 0 0 1 2 2 2
  spline S482 degree 2 poles (10.3762, -0.366) (10.3762, -0.5538) (10.2206, -0.8699) (10.07, -0.9811) knots 0 0 0 1 2 2 2
  spline S483 degree 2 poles (10.07, -0.9811) (9.9193, -1.0922) (9.4747, -1.2157) (9.1857, -1.2157) knots 0 0 0 1 2 2 2
  spline S484 degree 2 poles (9.1857, -1.2157) (8.8843, -1.2157) (8.4447, -1.0601) (8.2792, -0.9243) knots 0 0 0 1 2 2 2
  spline S485 degree 2 poles (8.2792, -0.9243) (8.131, -0.7983) (7.9606, -0.4451) (7.9606, -0.2499) knots 0 0 0 1 2 2 2
  spline S486 degree 2 poles (7.9606, -0.2499) (7.9606, -0.0795) (8.0371, 0.1749) (8.1162, 0.3157) knots 0 0 0 1 2 2 2
  line L340 (8.1162, 0.3157) -> (7.1282, 0.3157)
  line L341 (7.1282, 0.3157) -> (7.1282, 0.701)
  line L342 (7.1282, 0.701) -> (10.312, 0.701)
  line L343 (9.7563, 0.3157) -> (8.4348, 0.3157)
  spline S487 degree 2 poles (8.4348, 0.3157) (8.3656, 0.1724) (8.3138, -0.0548) (8.3138, -0.1857) knots 0 0 0 1 2 2 2
  spline S488 degree 2 poles (8.3138, -0.1857) (8.3138, -0.4821) (8.7584, -0.818) (9.1783, -0.818) knots 0 0 0 1 2 2 2
  spline S489 degree 2 poles (9.1783, -0.818) (9.5834, -0.818) (10.0107, -0.5612) (10.0107, -0.2771) knots 0 0 0 1 2 2 2
  spline S490 degree 2 poles (10.0107, -0.2771) (10.0107, -0.1264) (9.8724, 0.1798) (9.7563, 0.3157) knots 0 0 0 1 2 2 2
  line L344 (8.4373, 2.472) -> (8.4373, 2.4523)
  spline S491 degree 2 poles (8.4373, 2.4523) (8.4249, 2.4078) (8.42, 2.3115) (8.42, 2.2448) knots 0 0 0 1 2 2 2
  spline S492 degree 2 poles (8.42, 2.2448) (8.42, 2.0892) (8.5558, 1.7829) (8.6892, 1.6446) knots 0 0 0 1 2 2 2
  line L345 (8.6892, 1.6446) -> (10.312, 1.6446)
  line L346 (10.312, 1.6446) -> (10.312, 1.2592)
  line L347 (10.312, 1.2592) -> (8.0248, 1.2592)
  line L348 (8.0248, 1.2592) -> (8.0248, 1.6446)
  line L349 (8.0248, 1.6446) -> (8.3656, 1.6446)
  spline S493 degree 2 poles (8.3656, 1.6446) (8.1779, 1.8545) (8.0248, 2.1682) (8.0248, 2.3164) knots 0 0 0 1 2 2 2
  spline S494 degree 2 poles (8.0248, 2.3164) (8.0248, 2.3757) (8.0297, 2.435) (8.0371, 2.472) knots 0 0 0 1 2 2 2
  line L350 (8.0371, 2.472) -> (8.4373, 2.472)
  spline S495 degree 2 poles (9.1684, 4.6506) (9.7464, 4.6506) (10.3762, 4.0948) (10.3762, 3.6305) knots 0 0 0 1 2 2 2
  spline S496 degree 2 poles (10.3762, 3.6305) (10.3762, 3.1537) (9.7266, 2.6079) (9.1684, 2.6079) knots 0 0 0 1 2 2 2
  spline S497 degree 2 poles (9.1684, 2.6079) (8.5954, 2.6079) (7.9606, 3.171) (7.9606, 3.6305) knots 0 0 0 1 2 2 2
  spline S498 degree 2 poles (7.9606, 3.6305) (7.9606, 4.0948) (8.5929, 4.6506) (9.1684, 4.6506) knots 0 0 0 1 2 2 2
  spline S499 degree 2 poles (9.1684, 4.2529) (8.7238, 4.2529) (8.2915, 3.9293) (8.2915, 3.6305) knots 0 0 0 1 2 2 2
  spline S500 degree 2 poles (8.2915, 3.6305) (8.2915, 3.3316) (8.7238, 3.0055) (9.1684, 3.0055) knots 0 0 0 1 2 2 2
  spline S501 degree 2 poles (9.1684, 3.0055) (9.6006, 3.0055) (10.0453, 3.3316) (10.0453, 3.6305) knots 0 0 0 1 2 2 2
  spline S502 degree 2 poles (10.0453, 3.6305) (10.0453, 3.9269) (9.6081, 4.2529) (9.1684, 4.2529) knots 0 0 0 1 2 2 2
  spline S503 degree 2 poles (7.6123, 8.5408) (7.8148, 8.7137) (8.4076, 8.9064) (8.788, 8.9064) knots 0 0 0 1 2 2 2
  spline S504 degree 2 poles (8.788, 8.9064) (9.1585, 8.9064) (9.7587, 8.7187) (9.9613, 8.5408) knots 0 0 0 1 2 2 2
  spline S505 degree 2 poles (9.9613, 8.5408) (10.1737, 8.3531) (10.3762, 7.8566) (10.3762, 7.5578) knots 0 0 0 1 2 2 2
  spline S506 degree 2 poles (10.3762, 7.5578) (10.3762, 7.249) (10.1663, 6.755) (9.9613, 6.5747) knots 0 0 0 1 2 2 2
  spline S507 degree 2 poles (9.9613, 6.5747) (9.7587, 6.3993) (9.1635, 6.2116) (8.788, 6.2116) knots 0 0 0 1 2 2 2
  spline S508 degree 2 poles (8.788, 6.2116) (8.4052, 6.2116) (7.8222, 6.4018) (7.6123, 6.5772) knots 0 0 0 1 2 2 2
  spline S509 degree 2 poles (7.6123, 6.5772) (7.4097, 6.755) (7.1998, 7.2515) (7.1998, 7.5578) knots 0 0 0 1 2 2 2
  spline S510 degree 2 poles (7.1998, 7.5578) (7.1998, 7.869) (7.4172, 8.3679) (7.6123, 8.5408) knots 0 0 0 1 2 2 2
  spline S511 degree 2 poles (8.788, 8.484) (8.4867, 8.484) (8.0198, 8.3531) (7.8667, 8.2346) knots 0 0 0 1 2 2 2
  spline S512 degree 2 poles (7.8667, 8.2346) (7.7086, 8.1135) (7.5505, 7.7727) (7.5505, 7.5602) knots 0 0 0 1 2 2 2
  spline S513 degree 2 poles (7.5505, 7.5602) (7.5505, 7.3404) (7.7037, 7.0094) (7.8667, 6.8835) knots 0 0 0 1 2 2 2
  spline S514 degree 2 poles (7.8667, 6.8835) (8.0223, 6.7624) (8.4916, 6.634) (8.788, 6.634) knots 0 0 0 1 2 2 2
  spline S515 degree 2 poles (8.788, 6.634) (9.3882, 6.634) (10.0255, 7.1379) (10.0255, 7.5602) knots 0 0 0 1 2 2 2
  spline S516 degree 2 poles (10.0255, 7.5602) (10.0255, 7.9826) (9.3882, 8.484) (8.788, 8.484) knots 0 0 0 1 2 2 2
  line L351 (10.312, 11.0973) -> (10.312, 10.6255)
  line L352 (10.312, 10.6255) -> (9.4524, 10.0698)
  line L353 (9.4524, 10.0698) -> (10.312, 9.4992)
  line L354 (10.312, 9.4992) -> (10.312, 9.062)
  line L355 (10.312, 9.062) -> (9.1783, 9.8549)
  line L356 (9.1783, 9.8549) -> (8.0248, 9.0694)
  line L357 (8.0248, 9.0694) -> (8.0248, 9.5412)
  line L358 (8.0248, 9.5412) -> (8.8769, 10.0945)
  line L359 (8.8769, 10.0945) -> (8.0248, 10.6601)
  line L360 (8.0248, 10.6601) -> (8.0248, 11.0973)
  line L361 (8.0248, 11.0973) -> (9.1536, 10.3094)
  line L362 (9.1536, 10.3094) -> (10.312, 11.0973)
  line L363 (10.312, 11.7889) -> (10.312, 11.4036)
  line L364 (10.312, 11.4036) -> (7.1282, 11.4036)
  line L365 (7.1282, 11.4036) -> (7.1282, 11.7889)
  line L366 (7.1282, 11.7889) -> (10.312, 11.7889)
  spline S517 degree 2 poles (10.07, 13.6291) (10.1045, 13.5821) (10.228, 13.4241) (10.2651, 13.35) knots 0 0 0 1 2 2 2
  spline S518 degree 2 poles (10.2651, 13.35) (10.3194, 13.2487) (10.3762, 13.0585) (10.3762, 12.8856) knots 0 0 0 1 2 2 2
  spline S519 degree 2 poles (10.3762, 12.8856) (10.3762, 12.7448) (10.27, 12.4904) (10.1737, 12.3941) knots 0 0 0 1 2 2 2
  spline S520 degree 2 poles (10.1737, 12.3941) (10.0798, 12.3027) (9.8032, 12.1915) (9.65, 12.1915) knots 0 0 0 1 2 2 2
  spline S521 degree 2 poles (9.65, 12.1915) (9.4129, 12.1915) (9.077, 12.3916) (8.9807, 12.609) knots 0 0 0 1 2 2 2
  spline S522 degree 2 poles (8.9807, 12.609) (8.8918, 12.8016) (8.8251, 13.3253) (8.8078, 13.6291) knots 0 0 0 1 2 2 2
  line L367 (8.8078, 13.6291) -> (8.7337, 13.6291)
  spline S523 degree 2 poles (8.7337, 13.6291) (8.6003, 13.6291) (8.4348, 13.5476) (8.3879, 13.4735) knots 0 0 0 1 2 2 2
  spline S524 degree 2 poles (8.3879, 13.4735) (8.3409, 13.3994) (8.3113, 13.1869) (8.3113, 13.0733) knots 0 0 0 1 2 2 2
  spline S525 degree 2 poles (8.3113, 13.0733) (8.3113, 12.9399) (8.3903, 12.5793) (8.4669, 12.399) knots 0 0 0 1 2 2 2
  line L368 (8.4669, 12.399) -> (8.4669, 12.3768)
  line L369 (8.4669, 12.3768) -> (8.0742, 12.3768)
  spline S526 degree 2 poles (8.0742, 12.3768) (8.0445, 12.483) (7.9704, 12.8807) (7.9704, 13.0758) knots 0 0 0 1 2 2 2
  spline S527 degree 2 poles (7.9704, 13.0758) (7.9704, 13.3129) (8.0445, 13.6365) (8.1409, 13.7649) knots 0 0 0 1 2 2 2
  spline S528 degree 2 poles (8.1409, 13.7649) (8.2347, 13.8909) (8.5336, 14.0144) (8.7485, 14.0144) knots 0 0 0 1 2 2 2
  line L370 (8.7485, 14.0144) -> (10.312, 14.0144)
  line L371 (10.312, 14.0144) -> (10.312, 13.6291)
  line L372 (10.312, 13.6291) -> (10.07, 13.6291)
  line L373 (9.7488, 13.6291) -> (9.1141, 13.6291)
  spline S529 degree 2 poles (9.1141, 13.6291) (9.1264, 13.4908) (9.1684, 13.0733) (9.2079, 12.9424) knots 0 0 0 1 2 2 2
  spline S530 degree 2 poles (9.2079, 12.9424) (9.2548, 12.7893) (9.45, 12.5892) (9.6229, 12.5892) knots 0 0 0 1 2 2 2
  spline S531 degree 2 poles (9.6229, 12.5892) (9.8205, 12.5892) (10.0206, 12.8115) (10.0206, 13.0239) knots 0 0 0 1 2 2 2
  spline S532 degree 2 poles (10.0206, 13.0239) (10.0206, 13.2042) (9.8649, 13.5006) (9.7488, 13.6291) knots 0 0 0 1 2 2 2
  spline S533 degree 2 poles (10.3762, 15.1778) (10.7665, 15.1778) (11.1765, 14.7579) (11.1765, 14.3898) knots 0 0 0 1 2 2 2
  spline S534 degree 2 poles (11.1765, 14.3898) (11.1765, 14.3256) (11.1642, 14.1675) (11.1518, 14.091) knots 0 0 0 1 2 2 2
  line L374 (11.1518, 14.091) -> (10.806, 14.091)
  line L375 (10.806, 14.091) -> (10.806, 14.1132)
  spline S535 degree 2 poles (10.806, 14.1132) (10.8159, 14.1577) (10.8357, 14.2663) (10.8357, 14.3157) knots 0 0 0 1 2 2 2
  spline S536 degree 2 poles (10.8357, 14.3157) (10.8357, 14.4689) (10.7591, 14.669) (10.6776, 14.7159) knots 0 0 0 1 2 2 2
  spline S537 degree 2 poles (10.6776, 14.7159) (10.6035, 14.7628) (10.3787, 14.7925) (10.2182, 14.7925) knots 0 0 0 1 2 2 2
  line L376 (10.2182, 14.7925) -> (8.3434, 14.7925)
  line L377 (8.3434, 14.7925) -> (8.3434, 14.38)
  line L378 (8.3434, 14.38) -> (8.0248, 14.38)
  line L379 (8.0248, 14.38) -> (8.0248, 15.1778)
  line L380 (8.0248, 15.1778) -> (10.3762, 15.1778)
  line L381 (7.6444, 15.1802) -> (7.6444, 14.7431)
  line L382 (7.6444, 14.7431) -> (7.2443, 14.7431)
  line L383 (7.2443, 14.7431) -> (7.2443, 15.1802)
  line L384 (7.2443, 15.1802) -> (7.6444, 15.1802)
  line L385 (10.312, 17.7861) -> (7.6246, 17.7861)
  line L386 (7.6246, 17.7861) -> (7.6246, 16.7635)
  line L387 (7.6246, 16.7635) -> (7.264, 16.7635)
  line L388 (7.264, 16.7635) -> (7.264, 19.2138)
  line L389 (7.264, 19.2138) -> (7.6246, 19.2138)
  line L390 (7.6246, 19.2138) -> (7.6246, 18.1912)
  line L391 (7.6246, 18.1912) -> (10.312, 18.1912)
  line L392 (10.312, 18.1912) -> (10.312, 17.7861)
  line L393 (10.312, 20.9947) -> (10.312, 19.3151)
  line L394 (10.312, 19.3151) -> (10.0255, 19.3151)
  line L395 (10.0255, 19.3151) -> (8.3409, 20.5105)
  line L396 (8.3409, 20.5105) -> (8.3409, 19.3645)
  line L397 (8.3409, 19.3645) -> (8.0248, 19.3645)
  line L398 (8.0248, 19.3645) -> (8.0248, 20.9724)
  line L399 (8.0248, 20.9724) -> (8.299, 20.9724)
  line L400 (8.299, 20.9724) -> (9.9884, 19.772)
  line L401 (9.9884, 19.772) -> (9.9884, 20.9947)
  line L402 (9.9884, 20.9947) -> (10.312, 20.9947)
  line L403 (10.312, 23.1337) -> (10.312, 22.7484)
  line L404 (10.312, 22.7484) -> (10.0601, 22.7484)
  spline S538 degree 2 poles (10.0601, 22.7484) (10.2157, 22.5705) (10.3762, 22.2519) (10.3762, 22.0543) knots 0 0 0 1 2 2 2
  spline S539 degree 2 poles (10.3762, 22.0543) (10.3762, 21.9061) (10.2774, 21.6418) (10.1712, 21.5455) knots 0 0 0 1 2 2 2
  spline S540 degree 2 poles (10.1712, 21.5455) (10.065, 21.4467) (9.7414, 21.338) (9.5093, 21.338) knots 0 0 0 1 2 2 2
  line L405 (9.5093, 21.338) -> (8.0248, 21.338)
  line L406 (8.0248, 21.338) -> (8.0248, 21.7233)
  line L407 (8.0248, 21.7233) -> (9.3289, 21.7233)
  spline S541 degree 2 poles (9.3289, 21.7233) (9.5117, 21.7233) (9.7513, 21.7505) (9.8402, 21.7974) knots 0 0 0 1 2 2 2
  spline S542 degree 2 poles (9.8402, 21.7974) (9.9292, 21.8444) (10.0107, 22.0049) (10.0107, 22.1556) knots 0 0 0 1 2 2 2
  spline S543 degree 2 poles (10.0107, 22.1556) (10.0107, 22.2964) (9.8501, 22.615) (9.734, 22.7484) knots 0 0 0 1 2 2 2
  line L408 (9.734, 22.7484) -> (8.0248, 22.7484)
  line L409 (8.0248, 22.7484) -> (8.0248, 23.1337)
  line L410 (8.0248, 23.1337) -> (10.312, 23.1337)
  line L411 (10.312, 25.4876) -> (10.312, 25.1023)
  line L412 (10.312, 25.1023) -> (9.0078, 25.1023)
  spline S544 degree 2 poles (9.0078, 25.1023) (8.8498, 25.1023) (8.5781, 25.0727) (8.4966, 25.0282) knots 0 0 0 1 2 2 2
  spline S545 degree 2 poles (8.4966, 25.0282) (8.4101, 24.9813) (8.3261, 24.8133) (8.3261, 24.67) knots 0 0 0 1 2 2 2
  spline S546 degree 2 poles (8.3261, 24.67) (8.3261, 24.5268) (8.4793, 24.223) (8.6028, 24.0772) knots 0 0 0 1 2 2 2
  line L413 (8.6028, 24.0772) -> (10.312, 24.0772)
  line L414 (10.312, 24.0772) -> (10.312, 23.6919)
  line L415 (10.312, 23.6919) -> (8.0248, 23.6919)
  line L416 (8.0248, 23.6919) -> (8.0248, 24.0772)
  line L417 (8.0248, 24.0772) -> (8.2792, 24.0772)
  spline S547 degree 2 poles (8.2792, 24.0772) (8.1236, 24.2501) (7.9606, 24.5836) (7.9606, 24.7713) knots 0 0 0 1 2 2 2
  spline S548 degree 2 poles (7.9606, 24.7713) (7.9606, 25.1072) (8.4052, 25.4876) (8.8275, 25.4876) knots 0 0 0 1 2 2 2
  line L418 (8.8275, 25.4876) -> (10.312, 25.4876)
  line L419 (10.312, 27.807) -> (10.312, 27.4216)
  line L420 (10.312, 27.4216) -> (10.0601, 27.4216)
  spline S549 degree 2 poles (10.0601, 27.4216) (10.2157, 27.2438) (10.3762, 26.9252) (10.3762, 26.7276) knots 0 0 0 1 2 2 2
  spline S550 degree 2 poles (10.3762, 26.7276) (10.3762, 26.5794) (10.2774, 26.3151) (10.1712, 26.2187) knots 0 0 0 1 2 2 2
  spline S551 degree 2 poles (10.1712, 26.2187) (10.065, 26.1199) (9.7414, 26.0113) (9.5093, 26.0113) knots 0 0 0 1 2 2 2
  line L421 (9.5093, 26.0113) -> (8.0248, 26.0113)
  line L422 (8.0248, 26.0113) -> (8.0248, 26.3966)
  line L423 (8.0248, 26.3966) -> (9.3289, 26.3966)
  spline S552 degree 2 poles (9.3289, 26.3966) (9.5117, 26.3966) (9.7513, 26.4238) (9.8402, 26.4707) knots 0 0 0 1 2 2 2
  spline S553 degree 2 poles (9.8402, 26.4707) (9.9292, 26.5176) (10.0107, 26.6782) (10.0107, 26.8288) knots 0 0 0 1 2 2 2
  spline S554 degree 2 poles (10.0107, 26.8288) (10.0107, 26.9696) (9.8501, 27.2883) (9.734, 27.4216) knots 0 0 0 1 2 2 2
  line L424 (9.734, 27.4216) -> (8.0248, 27.4216)
  line L425 (8.0248, 27.4216) -> (8.0248, 27.807)
  line L426 (8.0248, 27.807) -> (10.312, 27.807)
  line L427 (10.312, 30.1609) -> (10.312, 29.7756)
  line L428 (10.312, 29.7756) -> (9.0078, 29.7756)
  spline S555 degree 2 poles (9.0078, 29.7756) (8.8498, 29.7756) (8.5781, 29.7459) (8.4966, 29.7015) knots 0 0 0 1 2 2 2
  spline S556 degree 2 poles (8.4966, 29.7015) (8.4101, 29.6545) (8.3261, 29.4866) (8.3261, 29.3433) knots 0 0 0 1 2 2 2
  spline S557 degree 2 poles (8.3261, 29.3433) (8.3261, 29.2001) (8.4793, 28.8962) (8.6028, 28.7505) knots 0 0 0 1 2 2 2
  line L429 (8.6028, 28.7505) -> (10.312, 28.7505)
  line L430 (10.312, 28.7505) -> (10.312, 28.3652)
  line L431 (10.312, 28.3652) -> (8.0248, 28.3652)
  line L432 (8.0248, 28.3652) -> (8.0248, 28.7505)
  line L433 (8.0248, 28.7505) -> (8.2792, 28.7505)
  spline S558 degree 2 poles (8.2792, 28.7505) (8.1236, 28.9234) (7.9606, 29.2569) (7.9606, 29.4446) knots 0 0 0 1 2 2 2
  spline S559 degree 2 poles (7.9606, 29.4446) (7.9606, 29.7805) (8.4052, 30.1609) (8.8275, 30.1609) knots 0 0 0 1 2 2 2
  line L434 (8.8275, 30.1609) -> (10.312, 30.1609)
  line L435 (15.3305, -5.5086) -> (15.3305, -7.3883)
  line L436 (15.3305, -7.3883) -> (14.8982, -7.3883)
  spline S560 degree 2 poles (14.8982, -7.3883) (14.708, -7.1857) (14.3548, -6.8251) (14.1646, -6.6522) knots 0 0 0 1 2 2 2
  spline S561 degree 2 poles (14.1646, -6.6522) (13.7818, -6.304) (13.3223, -6.0495) (13.0778, -6.0495) knots 0 0 0 1 2 2 2
  spline S562 degree 2 poles (13.0778, -6.0495) (12.9494, -6.0495) (12.7567, -6.1286) (12.695, -6.2002) knots 0 0 0 1 2 2 2
  spline S563 degree 2 poles (12.695, -6.2002) (12.6332, -6.2718) (12.5715, -6.4596) (12.5715, -6.5732) knots 0 0 0 1 2 2 2
  spline S564 degree 2 poles (12.5715, -6.5732) (12.5715, -6.6819) (12.6258, -6.9042) (12.6678, -7.0054) knots 0 0 0 1 2 2 2
  spline S565 degree 2 poles (12.6678, -7.0054) (12.7024, -7.0919) (12.8012, -7.2524) (12.8357, -7.3018) knots 0 0 0 1 2 2 2
  line L437 (12.8357, -7.3018) -> (12.8357, -7.3241)
  line L438 (12.8357, -7.3241) -> (12.401, -7.3241)
  spline S566 degree 2 poles (12.401, -7.3241) (12.3393, -7.1981) (12.2182, -6.7461) (12.2182, -6.5435) knots 0 0 0 1 2 2 2
  spline S567 degree 2 poles (12.2182, -6.5435) (12.2182, -6.1162) (12.6703, -5.6346) (13.0556, -5.6346) knots 0 0 0 1 2 2 2
  spline S568 degree 2 poles (13.0556, -5.6346) (13.2359, -5.6346) (13.5372, -5.7186) (13.6657, -5.7927) knots 0 0 0 1 2 2 2